goupille_circlip_adapter_v1 (Autodesk Fusion 360 design; units mm, degrees)
Autodesk Fusion 360 part; units mm, degrees
sketch "Sketch1" plane through (0, 0, 0) normal (1, 0, 0) x (0, 1, 0)
  circle A0 centre (0, 0) radius 5.1
  circle A1 centre (0, 0) radius 8
  circle A2 centre (0, 0) radius 4.1
  dimension "d1" = 10.2
  dimension "d2" = 16
  dimension "d3" = 8.2
  constraint coincident A0.centre A1.centre
  measures "d1" diameter of A0
  measures "d2" diameter of A1
  measures "d3" diameter of A2
extrude "Extrude1" add sketch "Sketch1" against normal blind 2.4 contours A0 | A1
extrude "Extrude2" add sketch "Sketch1" along normal blind 4 contours A1
